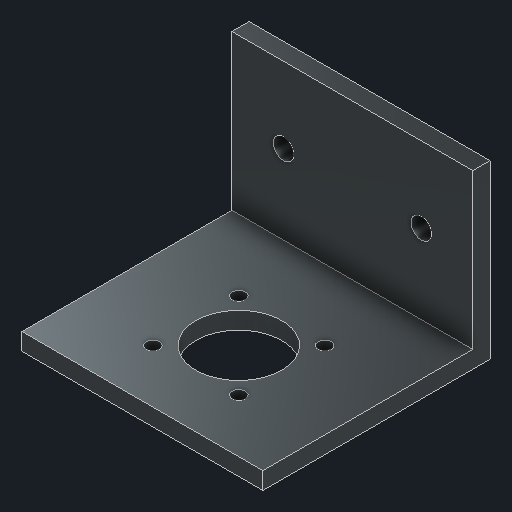
# Autodesk Inventor part: s1101mfd1513
Saved by Autodesk Inventor 2027.1 (Build 311270010, 270A)
## iProperties
Created: 2026-10-31
Part Number: s1101mfd1513
Material: Generic
Document SubType Name: Modeling
Designer: User
Density: 1 g/cm^3
Appearance: Iron Gray
Author: User
Autodesk Inventor part; units mm, degrees
ref_plane "YZ Plane" through (0, 0, 0) normal (1, 0, 0) x (0, 1, 0)
ref_plane "XZ Plane" through (0, 0, 0) normal (0, 1, 0) x (-1, 0, 0)
ref_plane "XY Plane" through (0, 0, 0) normal (0, 0, 1) x (1, 0, 0)
sketch "Sketch1" plane through (0, 0, 0) normal (1, 0, 0) x (0, 1, 0)
  line L0 (0, 0) -> (31.75, 0)
  line L1 (31.75, 0) -> (31.75, 3.175)
  line L2 (31.75, 3.175) -> (3.175, 3.175)
  line L3 (3.175, 3.175) -> (3.175, 41.91)
  line L4 (3.175, 41.91) -> (0, 41.91)
  line L5 (0, 41.91) -> (0, 0)
  constraints: 12 end point
extrude "Extrusion1" add sketch "Sketch1" along normal mid plane 44.45
sketch "Sketch2" plane through (0, 0, 0) normal (0, 0, 1) x (1, 0, 0)
  circle A0 centre (-12.7, 17.78) radius 1.905
  circle A1 centre (12.7, 17.78) radius 1.905
  constraints: 2 centre point
extrude "Extrusion2" cut sketch "Sketch2" along normal mid plane 7.62
sketch "Sketch3" plane through (0, 0, 0) normal (0, 1, 0) x (-1, 0, 0)
  circle A0 centre (0, 24.13) radius 7.9375
  circle A1 centre (7.9248, 16.2052) radius 1.2192
  circle A2 centre (7.9248, 32.0548) radius 1.2192
  circle A3 centre (-7.9248, 16.2052) radius 1.2192
  circle A4 centre (-7.9248, 32.0548) radius 1.2192
  constraints: 5 centre point
extrude "Extrusion3" cut sketch "Sketch3" along normal mid plane 7.62
body "Solid1"
